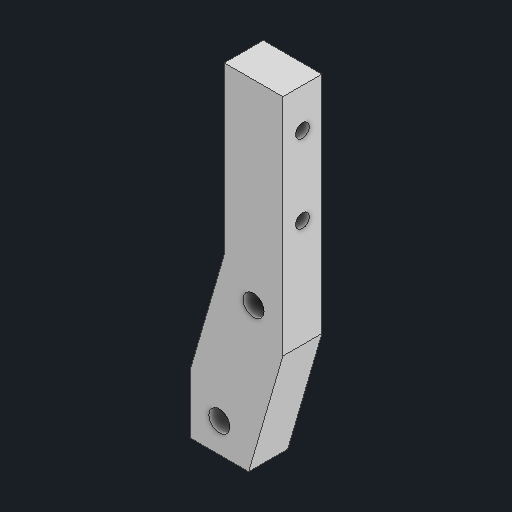
# Autodesk Inventor part: P4-01 Left finger
Saved by Autodesk Inventor 2027.1 (Build 311270010, 270A)
## iProperties
Created: 2026-10-21
Part Number: P4-01 Left finger
Material: Generic
Document SubType Name: Modeling
Designer: anshi
Mass: 6.94989 g
Surface Area: 35.5463 cm^2
Volume: 6.94989 cm^3
Density: 1 g/cm^3
Appearance: Default
Author: anshi
Autodesk Inventor part; units mm, degrees
ref_plane "YZ Plane" through (0, 0, 0) normal (1, 0, 0) x (0, 1, 0)
sketch "Dimensioned base profile" plane through (0, 0, 0) normal (0, 0, 1) x (1, 0, 0)
  line L0 (-6, -6) -> (6, -6)
  line L1 (6, -6) -> (13, 18)
  line L2 (13, 18) -> (13, 64)
  line L3 (13, 64) -> (1, 64)
  line L4 (1, 64) -> (1, 30)
  line L5 (1, 30) -> (-6, 6)
  line L6 (-6, 6) -> (-6, -6)
  circle A0 centre (0, 0) radius 2.15
  circle A1 centre (7, 24) radius 2.15
  constraints: 14 end point, 2 centre point
extrude "Thickness 8 mm" add sketch "Dimensioned base profile" along normal blind 8
ref_plane "Work Plane1" through (1, 0, 0) normal (1, 0, 0) x (0, 1, 0)
sketch "Pad cross-hole centres" plane through (1, 0, 0) normal (1, 0, 0) x (0, 1, 0)
  circle A0 centre (40, 4) radius 1.4
  circle A1 centre (56, 4) radius 1.4
  constraints: 2 centre point
extrude "Pad cross holes 2.8" cut sketch "Pad cross-hole centres" along normal blind 12
ref_plane "Work Plane2" through (1, 0, 0) normal (1, 0, 0) x (0, 1, 0)
sketch "M2.5 nut sockets AF5" plane through (1, 0, 0) normal (1, 0, 0) x (0, 1, 0)
  line L0 (42.8868, 4) -> (41.4434, 6.5)
  line L1 (41.4434, 6.5) -> (38.5566, 6.5)
  line L2 (38.5566, 6.5) -> (37.1132, 4)
  line L3 (37.1132, 4) -> (38.5566, 1.5)
  line L4 (38.5566, 1.5) -> (41.4434, 1.5)
  line L5 (41.4434, 1.5) -> (42.8868, 4)
  line L6 (58.8868, 4) -> (57.4434, 6.5)
  line L7 (57.4434, 6.5) -> (54.5566, 6.5)
  line L8 (54.5566, 6.5) -> (53.1132, 4)
  line L9 (53.1132, 4) -> (54.5566, 1.5)
  line L10 (54.5566, 1.5) -> (57.4434, 1.5)
  line L11 (57.4434, 1.5) -> (58.8868, 4)
  constraints: 24 end point
extrude "Side sockets depth 2" cut sketch "M2.5 nut sockets AF5" along normal blind 2
equation "\"NominalThickness\" = 8"
body "Solid1"
